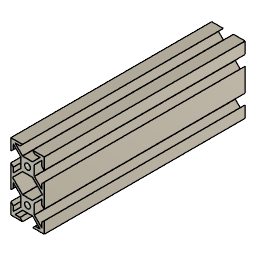
width_allum_double_v3 (Autodesk Fusion 360 design; units mm, degrees)
part number: 2026-11-05-11-32-20-513
Autodesk Fusion 360 part; units mm, degrees
sketch "Sketch1" plane through (0, 0, 0) normal (0, 1, 0) x (1, 0, 0)
  line L0 (-3, -13) -> (-3, -20)
  line L1 (10, -13) -> (3, -20)
  line L2 (-8.5, -5.5) -> (-8.5, -1.5)
  line L3 (-4, -14) -> (4, -14)
  line L4 (-4.5, -18.5) -> (-8.5, -18.5)
  line L5 (10, 0) -> (-10, 0)
  line L6 (-3, -7) -> (-10, -7)
  line L7 (-10, -7) -> (-3, 0)
  line L8 (10, -13) -> (10, -20)
  line L9 (-8.5, -14.5) -> (-4.5, -14.5)
  line L10 (0, -7.5) -> (0, 10)
  line L11 (-10, 0) -> (-10, -20)
  line L12 (-3, 0) -> (-3, -7)
  line L13 (-8.5, -18.5) -> (-8.5, -14.5)
  line L14 (-8.5, -1.5) -> (-4.5, -1.5)
  line L15 (10, 0) -> (-10, -20) construction
  line L16 (-4, -6) -> (4, -14) construction
  line L17 (4.5, -1.5) -> (8.5, -1.5)
  line L18 (8.5, -18.5) -> (4.5, -18.5)
  line L19 (-10, -20) -> (10, -20)
  line L20 (3, -20) -> (3, -13)
  line L21 (4, -6) -> (-4, -14) construction
  line L22 (-10, -13) -> (-3, -13)
  line L23 (10.5303, -0.5303) -> (-9.4697, -20.5303)
  line L24 (8.5, -14.5) -> (8.5, -18.5)
  line L25 (-4.5, -14.5) -> (-4.5, -18.5)
  line L26 (1.75, -10) -> (22.5, -10)
  line L27 (-4, -6) -> (-4, -14)
  line L28 (-4.5, -5.5) -> (-8.5, -5.5)
  line L29 (8.5, -5.5) -> (4.5, -5.5)
  line L30 (4, -6) -> (-4, -6)
  line L31 (-10, -13) -> (-3, -20)
  line L32 (10, -7) -> (3, -7)
  circle A0 centre (0, -10) radius 1.75
  line L33 (3, -13) -> (10, -13)
  line L34 (10, -20) -> (3, -20)
  line L35 (4.5, -14.5) -> (8.5, -14.5)
  line L36 (4.5, -18.5) -> (4.5, -14.5)
  line L37 (0, -10) -> (10, -20)
  line L38 (4, -14) -> (4, -6)
  line L39 (-4.5, -1.5) -> (-4.5, -5.5)
  line L40 (-10.5303, -0.5303) -> (9.4697, -20.5303)
  line L41 (3, -7) -> (3, 0)
  line L42 (-10, 0) -> (10, -20) construction
  line L43 (10, -7) -> (3, 0)
  line L44 (-9.4697, 0.5303) -> (10.5303, -19.4697)
  line L45 (8.5, -1.5) -> (8.5, -5.5)
  line L46 (9.4697, 0.5303) -> (-10.5303, -19.4697)
  line L47 (4.5, -5.5) -> (4.5, -1.5)
  line L48 (10, -20) -> (10, 0)
  line L49 (-3, 7) -> (-3, 0)
  line L50 (10, 7) -> (3, 0)
  line L51 (-8.5, 14.5) -> (-8.5, 18.5)
  line L52 (-4, 6) -> (4, 6)
  line L53 (-4.5, 1.5) -> (-8.5, 1.5)
  line L54 (10, 20) -> (-10, 20)
  line L55 (-3, 13) -> (-10, 13)
  line L56 (-10, 13) -> (-3, 20)
  line L57 (10, 7) -> (10, 0)
  line L58 (-8.5, 5.5) -> (-4.5, 5.5)
  line L59 (0, 12.5) -> (0, 30)
  line L60 (-10, 20) -> (-10, 0)
  line L61 (-3, 20) -> (-3, 13)
  line L62 (-8.5, 1.5) -> (-8.5, 5.5)
  line L63 (-8.5, 18.5) -> (-4.5, 18.5)
  line L64 (10, 20) -> (-10, 0) construction
  line L65 (-4, 14) -> (4, 6) construction
  line L66 (4.5, 18.5) -> (8.5, 18.5)
  line L67 (8.5, 1.5) -> (4.5, 1.5)
  line L68 (-10, 0) -> (10, 0)
  line L69 (3, 0) -> (3, 7)
  line L70 (4, 14) -> (-4, 6) construction
  line L71 (-10, 7) -> (-3, 7)
  line L72 (10.5303, 19.4697) -> (-9.4697, -0.5303)
  line L73 (8.5, 5.5) -> (8.5, 1.5)
  line L74 (-4.5, 5.5) -> (-4.5, 1.5)
  line L75 (1.75, 10) -> (22.5, 10)
  line L76 (-4, 14) -> (-4, 6)
  line L77 (-4.5, 14.5) -> (-8.5, 14.5)
  line L78 (8.5, 14.5) -> (4.5, 14.5)
  line L79 (4, 14) -> (-4, 14)
  line L80 (-10, 7) -> (-3, 0)
  line L81 (10, 13) -> (3, 13)
  circle A1 centre (0, 10) radius 1.75
  line L82 (3, 7) -> (10, 7)
  line L83 (10, 0) -> (3, 0)
  line L84 (4.5, 5.5) -> (8.5, 5.5)
  line L85 (4.5, 1.5) -> (4.5, 5.5)
  line L86 (0, 10) -> (10, 0)
  line L87 (4, 6) -> (4, 14)
  line L88 (-4.5, 18.5) -> (-4.5, 14.5)
  line L89 (-10.5303, 19.4697) -> (9.4697, -0.5303)
  line L90 (3, 13) -> (3, 20)
  line L91 (-10, 20) -> (10, 0) construction
  line L92 (10, 13) -> (3, 20)
  line L93 (-9.4697, 20.5303) -> (10.5303, 0.5303)
  line L94 (8.5, 18.5) -> (8.5, 14.5)
  line L95 (9.4697, 20.5303) -> (-10.5303, 0.5303)
  line L96 (4.5, 14.5) -> (4.5, 18.5)
  line L97 (10, 0) -> (10, 20)
  point P0 (0, -10)
  point P1 (0, -10)
  point P2 (0, 10)
  point P3 (0, 10)
  dimension "d1" = 1.5
  dimension "d2" = 0.75
  dimension "d3" = -1.5
  dimension "d5" = 360
  dimension "d6" = 20
  dimension "d7" = 20
  dimension "d8" = 10
  dimension "d9" = 10
  dimension "d10" = 8
  dimension "d11" = 8
  dimension "d12" = 7
  dimension "d13" = 7
  dimension "d14" = 3.5
  dimension "d15" = 1.5
  dimension "d16" = 0.75
  dimension "d17" = -1.5
  dimension "d19" = 360
  dimension "d20" = 20
  dimension "d21" = 20
  dimension "d22" = 10
  dimension "d23" = 10
  dimension "d24" = 8
  dimension "d25" = 8
  dimension "d26" = 7
  dimension "d27" = 7
  dimension "d28" = 3.5
  constraint horizontal L30
  constraint perpendicular L27 L30
  constraint parallel L3 L30
  constraint parallel L27 L38
  constraint coincident P1 L21
  constraint coincident P1 L16
  constraint coincident P1 P0
  constraint horizontal L34
  constraint vertical L20
  constraint horizontal L33
  constraint vertical L8
  constraint parallel L37 L42
  constraint symmetric L23.start L40.start L10
  constraint symmetric L23.end L40.end L10
  constraint symmetric L46.start L44.start L10
  constraint symmetric L44.end L46.end L10
  constraint symmetric L22.start L1.start L10
  constraint symmetric L0.end L1.end L10
  constraint symmetric L22.start L6.end L26
  constraint symmetric L0.end L7.end L26
  constraint symmetric L1.start L32.start L26
  constraint symmetric L1.end L41.end L26
  constraint horizontal L79
  constraint perpendicular L76 L79
  constraint parallel L52 L79
  constraint parallel L76 L87
  constraint coincident P3 L70
  constraint coincident P3 L65
  constraint coincident P3 P2
  constraint horizontal L83
  constraint vertical L69
  constraint horizontal L82
  constraint vertical L57
  constraint parallel L86 L91
  constraint symmetric L72.start L89.start L59
  constraint symmetric L72.end L89.end L59
  constraint symmetric L95.start L93.start L59
  constraint symmetric L93.end L95.end L59
  constraint symmetric L71.start L50.start L59
  constraint symmetric L7.end L41.end L59
  constraint symmetric L71.start L55.end L75
  constraint symmetric L7.end L56.end L75
  constraint symmetric L50.start L81.start L75
  constraint symmetric L41.end L90.end L75
  measures "d6" distance of L8.end L11.end
  measures "d7" distance of L5.end L11.end
  measures "d8" distance of P1 L5
  measures "d9" distance of P1 L48
  measures "d10" distance of L3.start L3.end
  measures "d11" distance of L16.start L3.start
  measures "d12" distance of L8.end L1.end
  measures "d13" distance of L8.end L1.start
  measures "d14" diameter of A0
  measures "d20" distance of L5.start L5.end
  measures "d21" distance of L54.end L5.end
  measures "d22" distance of P3 L54
  measures "d23" distance of P3 L97
  measures "d24" distance of L52.start L52.end
  measures "d25" distance of L65.start L52.start
  measures "d26" distance of L5.start L41.end
  measures "d27" distance of L5.start L50.start
  measures "d28" diameter of A1
extrude "Extrude1" add sketch "Sketch1" along normal mid plane 120 contours L0 L3 L22 L23 L27 A0 L46 | L0 L3 L22 L27 | L0 L3 L9 L22 L23 L25 L27 L46 | L3 L23 A0 L40 | L27 A0 L40 L46 | L4 L19 L23 L31 | L9 L23 L25 L31 L46 | L3 L20 A0 L37 L40 | L11 L13 L31 L46 | L6 L12 L27 L30 A0 L40 L44 | L1 L18 L19 L34 L40 | L4 L11 L13 L19 L23 L46 | L4 L13 L23 L31 L46 | L3 L20 L37 | L3 L20 L36 L37 L40 | L2 L7 L11 L40 | L6 L12 L27 L30 | L6 L12 L27 L28 L30 L39 L40 L44 | L18 L19 L34 L37 L40 | L33 L35 L37 L38 L44 | L33 L37 L38 | A0 L33 L37 L38 L44 | L1 L36 L37 L40 | L2 L5 L11 L14 L40 L44 L68 | L7 L28 L39 L40 L44 | L30 A0 L44 L46 | L1 L18 L37 L40 | L8 L24 L37 L44 L48 | L1 L35 L37 L44 | L26 A0 L38 L44 | L2 L7 L14 L40 L44 | L5 L53 L60 L62 L68 L72 L95 | L23 L30 L32 A0 L38 L41 L46 | L1 L24 L37 L44 | L1 L8 L24 L44 L48 | L23 L26 A0 L38 | L60 L62 L80 L95 | L53 L62 L72 L80 L95 | L23 L29 L30 L32 L38 L41 L46 L47 | L30 L32 L38 L41 | L49 L52 L58 L71 L72 L74 L76 L95 | L58 L72 L74 L80 L95 | L51 L56 L60 L89 | L23 L29 L43 L46 L47 | L10 L52 L72 A1 | L10 L52 A1 L89 | L23 L43 L45 L48 | L49 L52 L71 L76 | L49 L52 L71 L72 L76 A1 L95 | L55 L61 L76 L77 L79 L88 L89 L93 | L51 L54 L60 L63 L89 L93 | L76 A1 L89 L95 | L5 L46 L68 L83 L86 | L46 L67 L86 L89 | L5 L17 L23 L45 L46 L48 L68 L83 | L52 L69 L85 L86 L89 | L17 L23 L43 L45 L46 | L52 L69 A1 L86 L89 | L55 L61 L76 L79 | L55 L61 L76 L79 A1 L89 L93 | L56 L77 L88 L89 L93 | L51 L56 L63 L89 L93 | L57 L73 L86 L93 L97 | L50 L67 L86 L89 | L50 L85 L86 L89 | L52 L69 L86 | L54 L56 L63 L93 | L50 L57 L73 L93 L97 | L50 L73 L86 L93 | L50 L84 L86 L93 | L82 L84 L86 L87 L93 | L82 L86 L87 | A1 L82 L86 L87 L93 | L79 A1 L93 L95 | L75 A1 L87 L93 | L72 L79 L81 A1 L87 L90 L95 | L72 L75 A1 L87 | L54 L66 L92 L95 | L72 L92 L94 L97 | L72 L78 L79 L81 L87 L90 L95 L96 | L79 L81 L87 L90 | L54 L66 L72 L94 L95 L97 | L72 L78 L92 L95 L96 | L66 L72 L92 L94 L95
equation "d29 = ( 120 / 2 ) * 1 mm"
